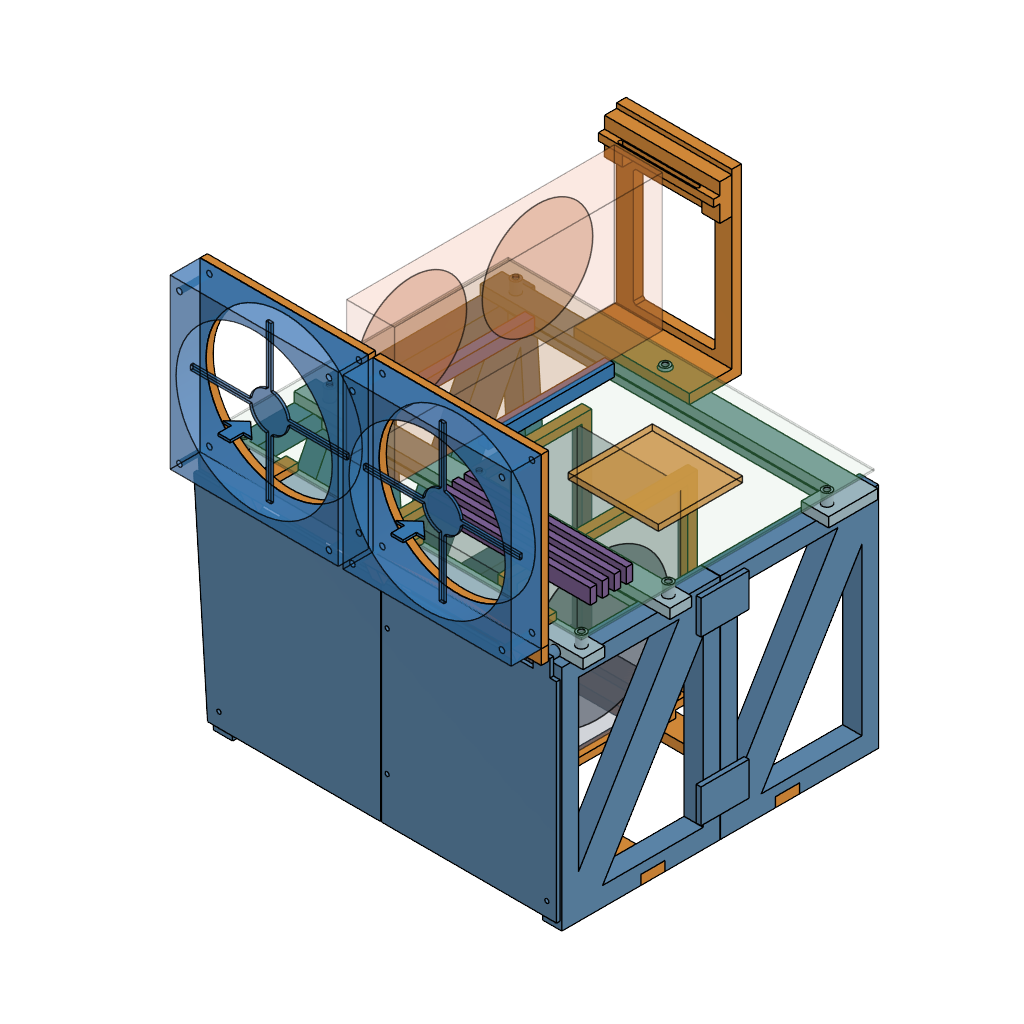
ATX_Desk_v04_layout (Autodesk Fusion 360 design; units mm, degrees)
part number: 2026-10-20-23-59-44-209
part number: 2026-10-20-23-59-44-522
part number: 2026-10-20-23-59-44-967
part number: 2026-10-20-23-59-45-768
part number: 2026-10-20-23-59-46-990
part number: 2026-10-20-23-59-48-547
part number: 2026-10-20-23-59-49-268
part number: 2026-10-20-23-59-50-114
part number: 2026-10-20-23-59-51-053
part number: 2026-10-20-23-59-51-964
part number: 2026-10-20-23-59-56-069
part number: 2026-10-21-00-00-01-103
part number: 2026-10-21-00-00-08-092
part number: 2026-10-21-00-00-09-158
part number: 2026-10-21-00-00-10-242
part number: 2026-10-21-00-00-23-562
part number: 2026-10-21-00-00-25-419
part number: 2026-10-21-00-00-27-273
part number: 2026-10-21-00-00-38-661
part number: 2026-10-21-00-00-46-426
part number: 2026-10-21-00-00-56-981
part number: 2026-10-21-00-01-04-262
part number: 2026-10-21-00-01-12-035
part number: 2026-10-21-00-01-25-487
part number: 2026-10-21-00-01-28-371
part number: 2026-10-21-00-01-43-062
part number: 2026-10-21-00-01-46-190
part number: 2026-10-21-00-02-02-158
part number: 2026-10-21-00-02-04-809
part number: 2026-10-21-00-02-14-600
part number: 2026-10-21-00-02-17-363
part number: 2026-10-21-00-02-20-116
part number: 2026-10-21-00-02-22-902
part number: 2026-10-21-00-02-25-724
part number: 2026-10-21-00-02-27-737
part number: 2026-10-21-00-14-16-300
part number: 2026-10-21-00-14-19-114
Autodesk Fusion 360 part; units mm, degrees
(part 1 of 2)
ref_plane "工作平面1" through (0, 0, 0) normal (0, 0, 1) x (1, 0, 0) in component "01_PCI_front_INSET_SIDE"
sketch "草图1" plane through (0, 0, 0) normal (0, 0, 1) x (1, 0, 0) in component "01_PCI_front_INSET_SIDE"
  line L0 (8.45, -10) -> (24.45, -10)
  line L1 (24.45, -10) -> (24.45, 121.72)
  line L2 (24.45, 121.72) -> (8.45, 121.72)
  line L3 (8.45, 121.72) -> (8.45, -10)
ref_plane "工作平面2" through (0, 0, 190) normal (0, 0, 1) x (1, 0, 0) in component "01_PCI_front_INSET_SIDE"
sketch "草图2" plane through (0, 0, 190) normal (0, 0, 1) x (1, 0, 0) in component "01_PCI_front_INSET_SIDE"
  line L0 (-4, -10) -> (12, -10)
  line L1 (12, -10) -> (12, 121.72)
  line L2 (12, 121.72) -> (-4, 121.72)
  line L3 (-4, 121.72) -> (-4, -10)
loft "Inward taper side frame" add profiles "草图1", "草图2" section 1 section 2 makes body 1 in component "01_PCI_front_INSET_SIDE"
ref_plane "工作平面3" through (-10, 0, 0) normal (1, 0, 0) x (0, 1, 0) in component "01_PCI_front_INSET_SIDE"
sketch "草图3" plane through (-10, 0, 0) normal (1, 0, 0) x (0, 0, -1) in component "01_PCI_front_INSET_SIDE"
  line L0 (-36, 4) -> (-176, 4)
  line L1 (-176, 4) -> (-176, 87.72)
  line L2 (-176, 87.72) -> (-36, 4)
extrude "Upper triangular opening" cut sketch "草图3" along normal blind 340 bodies 1 in component "01_PCI_front_INSET_SIDE"
ref_plane "工作平面4" through (-10, 0, 0) normal (1, 0, 0) x (0, 1, 0) in component "01_PCI_front_INSET_SIDE"
sketch "草图4" plane through (-10, 0, 0) normal (1, 0, 0) x (0, 0, -1) in component "01_PCI_front_INSET_SIDE"
  line L0 (-16, 24) -> (-16, 107.72)
  line L1 (-16, 107.72) -> (-154, 107.72)
  line L2 (-154, 107.72) -> (-16, 24)
extrude "Lower triangular opening" cut sketch "草图4" along normal blind 340 bodies 1 in component "01_PCI_front_INSET_SIDE"
ref_plane "工作平面5" through (0, 0, 0) normal (0, 0, 1) x (1, 0, 0) in component "01_PCI_front_INSET_SIDE"
sketch "草图5" plane through (0, 0, 0) normal (0, 0, 1) x (1, 0, 0) in component "01_PCI_front_INSET_SIDE"
  line L0 (-10, 55.92) -> (320, 55.92)
  line L1 (320, 55.92) -> (320, 75.92)
  line L2 (320, 75.92) -> (-10, 75.92)
  line L3 (-10, 75.92) -> (-10, 55.92)
extrude "Recess for bottom crossbar" cut sketch "草图5" along normal blind 8 bodies 1 in component "01_PCI_front_INSET_SIDE"
ref_plane "工作平面1" through (0, 0, 0) normal (0, 0, 1) x (1, 0, 0) in component "01_PCI_rear_INSET_SIDE"
sketch "草图1 (2)" plane through (0, 0, 0) normal (0, 0, 1) x (1, 0, 0) in component "01_PCI_rear_INSET_SIDE"
  line L0 (8.45, 122.12) -> (24.45, 122.12)
  line L1 (24.45, 122.12) -> (24.45, 253.84)
  line L2 (24.45, 253.84) -> (8.45, 253.84)
  line L3 (8.45, 253.84) -> (8.45, 122.12)
ref_plane "工作平面2" through (0, 0, 190) normal (0, 0, 1) x (1, 0, 0) in component "01_PCI_rear_INSET_SIDE"
sketch "草图2 (2)" plane through (0, 0, 190) normal (0, 0, 1) x (1, 0, 0) in component "01_PCI_rear_INSET_SIDE"
  line L0 (-4, 122.12) -> (12, 122.12)
  line L1 (12, 122.12) -> (12, 253.84)
  line L2 (12, 253.84) -> (-4, 253.84)
  line L3 (-4, 253.84) -> (-4, 122.12)
loft "Inward taper side frame'" add profiles "草图1 (2)", "草图2 (2)" section 1 section 2 separate body makes body 2 in component "01_PCI_rear_INSET_SIDE"
ref_plane "工作平面3" through (-10, 0, 0) normal (1, 0, 0) x (0, 1, 0) in component "01_PCI_rear_INSET_SIDE"
sketch "草图3 (2)" plane through (-10, 0, 0) normal (1, 0, 0) x (0, 0, -1) in component "01_PCI_rear_INSET_SIDE"
  line L0 (-36, 136.12) -> (-176, 136.12)
  line L1 (-176, 136.12) -> (-176, 219.84)
  line L2 (-176, 219.84) -> (-36, 136.12)
extrude "Upper triangular opening'" cut sketch "草图3 (2)" along normal blind 340 bodies 2 in component "01_PCI_rear_INSET_SIDE"
ref_plane "工作平面4" through (-10, 0, 0) normal (1, 0, 0) x (0, 1, 0) in component "01_PCI_rear_INSET_SIDE"
sketch "草图4 (2)" plane through (-10, 0, 0) normal (1, 0, 0) x (0, 0, -1) in component "01_PCI_rear_INSET_SIDE"
  line L0 (-16, 156.12) -> (-16, 239.84)
  line L1 (-16, 239.84) -> (-154, 239.84)
  line L2 (-154, 239.84) -> (-16, 156.12)
extrude "Lower triangular opening'" cut sketch "草图4 (2)" along normal blind 340 bodies 2 in component "01_PCI_rear_INSET_SIDE"
ref_plane "工作平面5" through (0, 0, 0) normal (0, 0, 1) x (1, 0, 0) in component "01_PCI_rear_INSET_SIDE"
sketch "草图5 (2)" plane through (0, 0, 0) normal (0, 0, 1) x (1, 0, 0) in component "01_PCI_rear_INSET_SIDE"
  line L0 (-10, 167.92) -> (320, 167.92)
  line L1 (320, 167.92) -> (320, 187.92)
  line L2 (320, 187.92) -> (-10, 187.92)
  line L3 (-10, 187.92) -> (-10, 167.92)
extrude "Recess for bottom crossbar'" cut sketch "草图5 (2)" along normal blind 8 bodies 2 in component "01_PCI_rear_INSET_SIDE"
ref_plane "工作平面1" through (0, 0, 0) normal (0, 0, 1) x (1, 0, 0) in component "01_CPU_front_VERTICAL_SIDE"
sketch "草图1 (3)" plane through (0, 0, 0) normal (0, 0, 1) x (1, 0, 0) in component "01_CPU_front_VERTICAL_SIDE"
  line L0 (282.45, -10) -> (298.45, -10)
  line L1 (298.45, -10) -> (298.45, 121.72)
  line L2 (298.45, 121.72) -> (282.45, 121.72)
  line L3 (282.45, 121.72) -> (282.45, -10)
ref_plane "工作平面2" through (0, 0, 190) normal (0, 0, 1) x (1, 0, 0) in component "01_CPU_front_VERTICAL_SIDE"
sketch "草图2 (3)" plane through (0, 0, 190) normal (0, 0, 1) x (1, 0, 0) in component "01_CPU_front_VERTICAL_SIDE"
  line L0 (282.45, -10) -> (298.45, -10)
  line L1 (298.45, -10) -> (298.45, 121.72)
  line L2 (298.45, 121.72) -> (282.45, 121.72)
  line L3 (282.45, 121.72) -> (282.45, -10)
loft "Inward taper side frame''" add profiles "草图1 (3)", "草图2 (3)" section 1 section 2 separate body makes body 3 in component "01_CPU_front_VERTICAL_SIDE"
ref_plane "工作平面3" through (-10, 0, 0) normal (1, 0, 0) x (0, 1, 0) in component "01_CPU_front_VERTICAL_SIDE"
sketch "草图3 (3)" plane through (-10, 0, 0) normal (1, 0, 0) x (0, 0, -1) in component "01_CPU_front_VERTICAL_SIDE"
  line L0 (-36, 4) -> (-176, 4)
  line L1 (-176, 4) -> (-176, 87.72)
  line L2 (-176, 87.72) -> (-36, 4)
extrude "Upper triangular opening''" cut sketch "草图3 (3)" along normal blind 340 bodies 3 in component "01_CPU_front_VERTICAL_SIDE"
ref_plane "工作平面4" through (-10, 0, 0) normal (1, 0, 0) x (0, 1, 0) in component "01_CPU_front_VERTICAL_SIDE"
sketch "草图4 (3)" plane through (-10, 0, 0) normal (1, 0, 0) x (0, 0, -1) in component "01_CPU_front_VERTICAL_SIDE"
  line L0 (-16, 24) -> (-16, 107.72)
  line L1 (-16, 107.72) -> (-154, 107.72)
  line L2 (-154, 107.72) -> (-16, 24)
extrude "Lower triangular opening''" cut sketch "草图4 (3)" along normal blind 340 bodies 3 in component "01_CPU_front_VERTICAL_SIDE"
ref_plane "工作平面5" through (0, 0, 0) normal (0, 0, 1) x (1, 0, 0) in component "01_CPU_front_VERTICAL_SIDE"
sketch "草图5 (3)" plane through (0, 0, 0) normal (0, 0, 1) x (1, 0, 0) in component "01_CPU_front_VERTICAL_SIDE"
  line L0 (-10, 55.92) -> (320, 55.92)
  line L1 (320, 55.92) -> (320, 75.92)
  line L2 (320, 75.92) -> (-10, 75.92)
  line L3 (-10, 75.92) -> (-10, 55.92)
extrude "Recess for bottom crossbar''" cut sketch "草图5 (3)" along normal blind 8 bodies 3 in component "01_CPU_front_VERTICAL_SIDE"
ref_plane "工作平面1" through (0, 0, 0) normal (0, 0, 1) x (1, 0, 0) in component "01_CPU_rear_VERTICAL_SIDE"
sketch "草图1 (4)" plane through (0, 0, 0) normal (0, 0, 1) x (1, 0, 0) in component "01_CPU_rear_VERTICAL_SIDE"
  line L0 (282.45, 122.12) -> (298.45, 122.12)
  line L1 (298.45, 122.12) -> (298.45, 253.84)
  line L2 (298.45, 253.84) -> (282.45, 253.84)
  line L3 (282.45, 253.84) -> (282.45, 122.12)
ref_plane "工作平面2" through (0, 0, 190) normal (0, 0, 1) x (1, 0, 0) in component "01_CPU_rear_VERTICAL_SIDE"
sketch "草图2 (4)" plane through (0, 0, 190) normal (0, 0, 1) x (1, 0, 0) in component "01_CPU_rear_VERTICAL_SIDE"
  line L0 (282.45, 122.12) -> (298.45, 122.12)
  line L1 (298.45, 122.12) -> (298.45, 253.84)
  line L2 (298.45, 253.84) -> (282.45, 253.84)
  line L3 (282.45, 253.84) -> (282.45, 122.12)
loft "Inward taper side frame'''" add profiles "草图1 (4)", "草图2 (4)" section 1 section 2 separate body makes body 4 in component "01_CPU_rear_VERTICAL_SIDE"
ref_plane "工作平面3" through (-10, 0, 0) normal (1, 0, 0) x (0, 1, 0) in component "01_CPU_rear_VERTICAL_SIDE"
sketch "草图3 (4)" plane through (-10, 0, 0) normal (1, 0, 0) x (0, 0, -1) in component "01_CPU_rear_VERTICAL_SIDE"
  line L0 (-36, 136.12) -> (-176, 136.12)
  line L1 (-176, 136.12) -> (-176, 219.84)
  line L2 (-176, 219.84) -> (-36, 136.12)
extrude "Upper triangular opening'''" cut sketch "草图3 (4)" along normal blind 340 bodies 4 in component "01_CPU_rear_VERTICAL_SIDE"
ref_plane "工作平面4" through (-10, 0, 0) normal (1, 0, 0) x (0, 1, 0) in component "01_CPU_rear_VERTICAL_SIDE"
sketch "草图4 (4)" plane through (-10, 0, 0) normal (1, 0, 0) x (0, 0, -1) in component "01_CPU_rear_VERTICAL_SIDE"
  line L0 (-16, 156.12) -> (-16, 239.84)
  line L1 (-16, 239.84) -> (-154, 239.84)
  line L2 (-154, 239.84) -> (-16, 156.12)
extrude "Lower triangular opening'''" cut sketch "草图4 (4)" along normal blind 340 bodies 4 in component "01_CPU_rear_VERTICAL_SIDE"
ref_plane "工作平面5" through (0, 0, 0) normal (0, 0, 1) x (1, 0, 0) in component "01_CPU_rear_VERTICAL_SIDE"
sketch "草图5 (4)" plane through (0, 0, 0) normal (0, 0, 1) x (1, 0, 0) in component "01_CPU_rear_VERTICAL_SIDE"
  line L0 (-10, 167.92) -> (320, 167.92)
  line L1 (320, 167.92) -> (320, 187.92)
  line L2 (320, 187.92) -> (-10, 187.92)
  line L3 (-10, 187.92) -> (-10, 167.92)
extrude "Recess for bottom crossbar'''" cut sketch "草图5 (4)" along normal blind 8 bodies 4 in component "01_CPU_rear_VERTICAL_SIDE"
ref_plane "工作平面1" through (0, 0, 22) normal (0, 0, 1) x (1, 0, 0) in component "02_PCI_low_SEAM_PLATE"
sketch "草图1 (5)" plane through (0, 0, 22) normal (0, 0, 1) x (1, 0, 0) in component "02_PCI_low_SEAM_PLATE"
  line L0 (3.0084, 101.92) -> (7.0084, 101.92)
  line L1 (7.0084, 101.92) -> (7.0084, 141.92)
  line L2 (7.0084, 141.92) -> (3.0084, 141.92)
  line L3 (3.0084, 141.92) -> (3.0084, 101.92)
ref_plane "工作平面2" through (0, 0, 50) normal (0, 0, 1) x (1, 0, 0) in component "02_PCI_low_SEAM_PLATE"
sketch "草图2 (5)" plane through (0, 0, 50) normal (0, 0, 1) x (1, 0, 0) in component "02_PCI_low_SEAM_PLATE"
  line L0 (1.1737, 101.92) -> (5.1737, 101.92)
  line L1 (5.1737, 101.92) -> (5.1737, 141.92)
  line L2 (5.1737, 141.92) -> (1.1737, 141.92)
  line L3 (1.1737, 141.92) -> (1.1737, 101.92)
loft "Taper matching seam plate - screw detail pending" add profiles "草图1 (5)", "草图2 (5)" section 1 section 2 separate body makes body 5 in component "02_PCI_low_SEAM_PLATE"
ref_plane "工作平面1" through (0, 0, 158) normal (0, 0, 1) x (1, 0, 0) in component "02_PCI_high_SEAM_PLATE"
sketch "草图1 (6)" plane through (0, 0, 158) normal (0, 0, 1) x (1, 0, 0) in component "02_PCI_high_SEAM_PLATE"
  line L0 (-5.9032, 101.92) -> (-1.9032, 101.92)
  line L1 (-1.9032, 101.92) -> (-1.9032, 141.92)
  line L2 (-1.9032, 141.92) -> (-5.9032, 141.92)
  line L3 (-5.9032, 141.92) -> (-5.9032, 101.92)
ref_plane "工作平面2" through (0, 0, 186) normal (0, 0, 1) x (1, 0, 0) in component "02_PCI_high_SEAM_PLATE"
sketch "草图2 (6)" plane through (0, 0, 186) normal (0, 0, 1) x (1, 0, 0) in component "02_PCI_high_SEAM_PLATE"
  line L0 (-7.7379, 101.92) -> (-3.7379, 101.92)
  line L1 (-3.7379, 101.92) -> (-3.7379, 141.92)
  line L2 (-3.7379, 141.92) -> (-7.7379, 141.92)
  line L3 (-7.7379, 141.92) -> (-7.7379, 101.92)
loft "Taper matching seam plate - screw detail pending'" add profiles "草图1 (6)", "草图2 (6)" section 1 section 2 separate body makes body 6 in component "02_PCI_high_SEAM_PLATE"
ref_plane "工作平面1" through (0, 0, 22) normal (0, 0, 1) x (1, 0, 0) in component "02_CPU_low_SEAM_PLATE"
sketch "草图1 (7)" plane through (0, 0, 22) normal (0, 0, 1) x (1, 0, 0) in component "02_CPU_low_SEAM_PLATE"
  line L0 (298.45, 101.92) -> (302.45, 101.92)
  line L1 (302.45, 101.92) -> (302.45, 141.92)
  line L2 (302.45, 141.92) -> (298.45, 141.92)
  line L3 (298.45, 141.92) -> (298.45, 101.92)
ref_plane "工作平面2" through (0, 0, 50) normal (0, 0, 1) x (1, 0, 0) in component "02_CPU_low_SEAM_PLATE"
sketch "草图2 (7)" plane through (0, 0, 50) normal (0, 0, 1) x (1, 0, 0) in component "02_CPU_low_SEAM_PLATE"
  line L0 (298.45, 101.92) -> (302.45, 101.92)
  line L1 (302.45, 101.92) -> (302.45, 141.92)
  line L2 (302.45, 141.92) -> (298.45, 141.92)
  line L3 (298.45, 141.92) -> (298.45, 101.92)
loft "Taper matching seam plate - screw detail pending''" add profiles "草图1 (7)", "草图2 (7)" section 1 section 2 separate body makes body 7 in component "02_CPU_low_SEAM_PLATE"
ref_plane "工作平面1" through (0, 0, 158) normal (0, 0, 1) x (1, 0, 0) in component "02_CPU_high_SEAM_PLATE"
sketch "草图1 (8)" plane through (0, 0, 158) normal (0, 0, 1) x (1, 0, 0) in component "02_CPU_high_SEAM_PLATE"
  line L0 (298.45, 101.92) -> (302.45, 101.92)
  line L1 (302.45, 101.92) -> (302.45, 141.92)
  line L2 (302.45, 141.92) -> (298.45, 141.92)
  line L3 (298.45, 141.92) -> (298.45, 101.92)
ref_plane "工作平面2" through (0, 0, 186) normal (0, 0, 1) x (1, 0, 0) in component "02_CPU_high_SEAM_PLATE"
sketch "草图2 (8)" plane through (0, 0, 186) normal (0, 0, 1) x (1, 0, 0) in component "02_CPU_high_SEAM_PLATE"
  line L0 (298.45, 101.92) -> (302.45, 101.92)
  line L1 (302.45, 101.92) -> (302.45, 141.92)
  line L2 (302.45, 141.92) -> (298.45, 141.92)
  line L3 (298.45, 141.92) -> (298.45, 101.92)
loft "Taper matching seam plate - screw detail pending'''" add profiles "草图1 (8)", "草图2 (8)" section 1 section 2 separate body makes body 8 in component "02_CPU_high_SEAM_PLATE"
ref_plane "工作平面1" through (0, 0, 190) normal (0, 0, 1) x (1, 0, 0) in component "03_FRONT_MOTHERBOARD_BEAM"
sketch "草图1 (9)" plane through (0, 0, 190) normal (0, 0, 1) x (1, 0, 0) in component "03_FRONT_MOTHERBOARD_BEAM"
  line L0 (-4, -2.65) -> (308.8, -2.65)
  line L1 (308.8, -2.65) -> (308.8, 15.35)
  line L2 (308.8, 15.35) -> (-4, 15.35)
  line L3 (-4, 15.35) -> (-4, -2.65)
extrude "Upper beam flange" add sketch "草图1 (9)" along normal blind 8 separate body makes body 9 in component "03_FRONT_MOTHERBOARD_BEAM"
ref_plane "工作平面2" through (0, 0, 178) normal (0, 0, 1) x (1, 0, 0) in component "03_FRONT_MOTHERBOARD_BEAM"
sketch "草图2 (9)" plane through (0, 0, 178) normal (0, 0, 1) x (1, 0, 0) in component "03_FRONT_MOTHERBOARD_BEAM"
  line L0 (14, 2.35) -> (281.45, 2.35)
  line L1 (281.45, 2.35) -> (281.45, 10.35)
  line L2 (281.45, 10.35) -> (14, 10.35)
  line L3 (14, 10.35) -> (14, 2.35)
extrude "Underside rib" add sketch "草图2 (9)" along normal blind 12 bodies 9 in component "03_FRONT_MOTHERBOARD_BEAM"
ref_plane "工作平面3" through (14, 0, 0) normal (1, 0, 0) x (0, 1, 0) in component "03_FRONT_MOTHERBOARD_BEAM"
sketch "草图3 (5)" plane through (14, 0, 0) normal (1, 0, 0) x (0, 0, -1) in component "03_FRONT_MOTHERBOARD_BEAM"
  line L0 (-184, 2.35) -> (-184, 10.35)
  line L1 (-184, 10.35) -> (-190, 15.35)
  line L2 (-190, 15.35) -> (-190, -2.65)
  line L3 (-190, -2.65) -> (-184, 2.35)
extrude "Printable rib transition" add sketch "草图3 (5)" along normal blind 267.45 bodies 9 in component "03_FRONT_MOTHERBOARD_BEAM"
ref_plane "工作平面4" through (0, 0, 198) normal (0, 0, 1) x (1, 0, 0) in component "03_FRONT_MOTHERBOARD_BEAM"
sketch "草图4 (5)" plane through (0, 0, 198) normal (0, 0, 1) x (1, 0, 0) in component "03_FRONT_MOTHERBOARD_BEAM"
  circle A0 centre (16.51, 6.35) radius 4
extrude "Motherboard mount 7" add sketch "草图4 (5)" along normal blind 10 bodies 9 in component "03_FRONT_MOTHERBOARD_BEAM"
ref_plane "工作平面5" through (0, 0, 203.1) normal (0, 0, 1) x (1, 0, 0) in component "03_FRONT_MOTHERBOARD_BEAM"
sketch "草图5 (5)" plane through (0, 0, 203.1) normal (0, 0, 1) x (1, 0, 0) in component "03_FRONT_MOTHERBOARD_BEAM"
  circle A0 centre (16.51, 6.35) radius 2.35
extrude "M3 insert pocket 7" cut sketch "草图5 (5)" along normal blind 4.9 bodies 9 in component "03_FRONT_MOTHERBOARD_BEAM"
ref_plane "工作平面6" through (0, 0, 198) normal (0, 0, 1) x (1, 0, 0) in component "03_FRONT_MOTHERBOARD_BEAM"
sketch "草图6" plane through (0, 0, 198) normal (0, 0, 1) x (1, 0, 0) in component "03_FRONT_MOTHERBOARD_BEAM"
  circle A0 centre (140.97, 6.35) radius 4
extrude "Motherboard mount 8" add sketch "草图6" along normal blind 10 bodies 9 in component "03_FRONT_MOTHERBOARD_BEAM"
ref_plane "工作平面7" through (0, 0, 203.1) normal (0, 0, 1) x (1, 0, 0) in component "03_FRONT_MOTHERBOARD_BEAM"
sketch "草图7" plane through (0, 0, 203.1) normal (0, 0, 1) x (1, 0, 0) in component "03_FRONT_MOTHERBOARD_BEAM"
  circle A0 centre (140.97, 6.35) radius 2.35
extrude "M3 insert pocket 8" cut sketch "草图7" along normal blind 4.9 bodies 9 in component "03_FRONT_MOTHERBOARD_BEAM"
ref_plane "工作平面8" through (0, 0, 198) normal (0, 0, 1) x (1, 0, 0) in component "03_FRONT_MOTHERBOARD_BEAM"
sketch "草图8" plane through (0, 0, 198) normal (0, 0, 1) x (1, 0, 0) in component "03_FRONT_MOTHERBOARD_BEAM"
  circle A0 centre (298.45, 6.35) radius 4
extrude "Motherboard mount 9" add sketch "草图8" along normal blind 10 bodies 9 in component "03_FRONT_MOTHERBOARD_BEAM"
ref_plane "工作平面9" through (0, 0, 203.1) normal (0, 0, 1) x (1, 0, 0) in component "03_FRONT_MOTHERBOARD_BEAM"
sketch "草图9" plane through (0, 0, 203.1) normal (0, 0, 1) x (1, 0, 0) in component "03_FRONT_MOTHERBOARD_BEAM"
  circle A0 centre (298.45, 6.35) radius 2.35
extrude "M3 insert pocket 9" cut sketch "草图9" along normal blind 4.9 bodies 9 in component "03_FRONT_MOTHERBOARD_BEAM"
ref_plane "工作平面1" through (0, 0, 190) normal (0, 0, 1) x (1, 0, 0) in component "03_MID_MOTHERBOARD_BEAM"
sketch "草图1 (10)" plane through (0, 0, 190) normal (0, 0, 1) x (1, 0, 0) in component "03_MID_MOTHERBOARD_BEAM"
  line L0 (-4, 69.74) -> (308.8, 69.74)
  line L1 (308.8, 69.74) -> (308.8, 87.74)
  line L2 (308.8, 87.74) -> (-4, 87.74)
  line L3 (-4, 87.74) -> (-4, 69.74)
extrude "Upper beam flange'" add sketch "草图1 (10)" along normal blind 8 separate body makes body 10 in component "03_MID_MOTHERBOARD_BEAM"
ref_plane "工作平面2" through (0, 0, 178) normal (0, 0, 1) x (1, 0, 0) in component "03_MID_MOTHERBOARD_BEAM"
sketch "草图2 (10)" plane through (0, 0, 178) normal (0, 0, 1) x (1, 0, 0) in component "03_MID_MOTHERBOARD_BEAM"
  line L0 (14, 74.74) -> (281.45, 74.74)
  line L1 (281.45, 74.74) -> (281.45, 82.74)
  line L2 (281.45, 82.74) -> (14, 82.74)
  line L3 (14, 82.74) -> (14, 74.74)
extrude "Underside rib'" add sketch "草图2 (10)" along normal blind 12 bodies 10 in component "03_MID_MOTHERBOARD_BEAM"
ref_plane "工作平面3" through (14, 0, 0) normal (1, 0, 0) x (0, 1, 0) in component "03_MID_MOTHERBOARD_BEAM"
sketch "草图3 (6)" plane through (14, 0, 0) normal (1, 0, 0) x (0, 0, -1) in component "03_MID_MOTHERBOARD_BEAM"
  line L0 (-184, 74.74) -> (-184, 82.74)
  line L1 (-184, 82.74) -> (-190, 87.74)
  line L2 (-190, 87.74) -> (-190, 69.74)
  line L3 (-190, 69.74) -> (-184, 74.74)
extrude "Printable rib transition'" add sketch "草图3 (6)" along normal blind 267.45 bodies 10 in component "03_MID_MOTHERBOARD_BEAM"
ref_plane "工作平面4" through (0, 0, 198) normal (0, 0, 1) x (1, 0, 0) in component "03_MID_MOTHERBOARD_BEAM"
sketch "草图4 (6)" plane through (0, 0, 198) normal (0, 0, 1) x (1, 0, 0) in component "03_MID_MOTHERBOARD_BEAM"
  circle A0 centre (16.51, 78.74) radius 4
extrude "Motherboard mount 4" add sketch "草图4 (6)" along normal blind 10 bodies 10 in component "03_MID_MOTHERBOARD_BEAM"
ref_plane "工作平面5" through (0, 0, 203.1) normal (0, 0, 1) x (1, 0, 0) in component "03_MID_MOTHERBOARD_BEAM"
sketch "草图5 (6)" plane through (0, 0, 203.1) normal (0, 0, 1) x (1, 0, 0) in component "03_MID_MOTHERBOARD_BEAM"
  circle A0 centre (16.51, 78.74) radius 2.35
extrude "M3 insert pocket 4" cut sketch "草图5 (6)" along normal blind 4.9 bodies 10 in component "03_MID_MOTHERBOARD_BEAM"
ref_plane "工作平面6" through (0, 0, 198) normal (0, 0, 1) x (1, 0, 0) in component "03_MID_MOTHERBOARD_BEAM"
sketch "草图6 (2)" plane through (0, 0, 198) normal (0, 0, 1) x (1, 0, 0) in component "03_MID_MOTHERBOARD_BEAM"
  circle A0 centre (140.97, 78.74) radius 4
extrude "Motherboard mount 5" add sketch "草图6 (2)" along normal blind 10 bodies 10 in component "03_MID_MOTHERBOARD_BEAM"
ref_plane "工作平面7" through (0, 0, 203.1) normal (0, 0, 1) x (1, 0, 0) in component "03_MID_MOTHERBOARD_BEAM"
sketch "草图7 (2)" plane through (0, 0, 203.1) normal (0, 0, 1) x (1, 0, 0) in component "03_MID_MOTHERBOARD_BEAM"
  circle A0 centre (140.97, 78.74) radius 2.35
extrude "M3 insert pocket 5" cut sketch "草图7 (2)" along normal blind 4.9 bodies 10 in component "03_MID_MOTHERBOARD_BEAM"
ref_plane "工作平面8" through (0, 0, 198) normal (0, 0, 1) x (1, 0, 0) in component "03_MID_MOTHERBOARD_BEAM"
sketch "草图8 (2)" plane through (0, 0, 198) normal (0, 0, 1) x (1, 0, 0) in component "03_MID_MOTHERBOARD_BEAM"
  circle A0 centre (298.45, 78.74) radius 4
extrude "Motherboard mount 6" add sketch "草图8 (2)" along normal blind 10 bodies 10 in component "03_MID_MOTHERBOARD_BEAM"
ref_plane "工作平面9" through (0, 0, 203.1) normal (0, 0, 1) x (1, 0, 0) in component "03_MID_MOTHERBOARD_BEAM"
sketch "草图9 (2)" plane through (0, 0, 203.1) normal (0, 0, 1) x (1, 0, 0) in component "03_MID_MOTHERBOARD_BEAM"
  circle A0 centre (298.45, 78.74) radius 2.35
extrude "M3 insert pocket 6" cut sketch "草图9 (2)" along normal blind 4.9 bodies 10 in component "03_MID_MOTHERBOARD_BEAM"
ref_plane "工作平面1" through (0, 0, 190) normal (0, 0, 1) x (1, 0, 0) in component "03_REAR_MOTHERBOARD_BEAM"
sketch "草图1 (11)" plane through (0, 0, 190) normal (0, 0, 1) x (1, 0, 0) in component "03_REAR_MOTHERBOARD_BEAM"
  line L0 (-4, 224.68) -> (308.8, 224.68)
  line L1 (308.8, 224.68) -> (308.8, 242.68)
  line L2 (308.8, 242.68) -> (-4, 242.68)
  line L3 (-4, 242.68) -> (-4, 224.68)
extrude "Upper beam flange''" add sketch "草图1 (11)" along normal blind 8 separate body makes body 11 in component "03_REAR_MOTHERBOARD_BEAM"
ref_plane "工作平面2" through (0, 0, 178) normal (0, 0, 1) x (1, 0, 0) in component "03_REAR_MOTHERBOARD_BEAM"
sketch "草图2 (11)" plane through (0, 0, 178) normal (0, 0, 1) x (1, 0, 0) in component "03_REAR_MOTHERBOARD_BEAM"
  line L0 (14, 229.68) -> (281.45, 229.68)
  line L1 (281.45, 229.68) -> (281.45, 237.68)
  line L2 (281.45, 237.68) -> (14, 237.68)
  line L3 (14, 237.68) -> (14, 229.68)
extrude "Underside rib''" add sketch "草图2 (11)" along normal blind 12 bodies 11 in component "03_REAR_MOTHERBOARD_BEAM"
ref_plane "工作平面3" through (14, 0, 0) normal (1, 0, 0) x (0, 1, 0) in component "03_REAR_MOTHERBOARD_BEAM"
sketch "草图3 (7)" plane through (14, 0, 0) normal (1, 0, 0) x (0, 0, -1) in component "03_REAR_MOTHERBOARD_BEAM"
  line L0 (-184, 229.68) -> (-184, 237.68)
  line L1 (-184, 237.68) -> (-190, 242.68)
  line L2 (-190, 242.68) -> (-190, 224.68)
  line L3 (-190, 224.68) -> (-184, 229.68)
extrude "Printable rib transition''" add sketch "草图3 (7)" along normal blind 267.45 bodies 11 in component "03_REAR_MOTHERBOARD_BEAM"
ref_plane "工作平面4" through (0, 0, 190) normal (0, 0, 1) x (1, 0, 0) in component "03_REAR_MOTHERBOARD_BEAM"
sketch "草图4 (7)" plane through (0, 0, 190) normal (0, 0, 1) x (1, 0, 0) in component "03_REAR_MOTHERBOARD_BEAM"
  line L0 (286, 201.82) -> (308.8, 201.82)
  line L1 (308.8, 201.82) -> (308.8, 233.68)
  line L2 (308.8, 233.68) -> (286, 233.68)
  line L3 (286, 233.68) -> (286, 201.82)
extrude "Staggered hole 3 pad" add sketch "草图4 (7)" along normal blind 8 bodies 11 in component "03_REAR_MOTHERBOARD_BEAM"
ref_plane "工作平面5" through (0, 0, 198) normal (0, 0, 1) x (1, 0, 0) in component "03_REAR_MOTHERBOARD_BEAM"
sketch "草图5 (7)" plane through (0, 0, 198) normal (0, 0, 1) x (1, 0, 0) in component "03_REAR_MOTHERBOARD_BEAM"
  circle A0 centre (16.51, 233.68) radius 4
extrude "Motherboard mount 1" add sketch "草图5 (7)" along normal blind 10 bodies 11 in component "03_REAR_MOTHERBOARD_BEAM"
ref_plane "工作平面6" through (0, 0, 203.1) normal (0, 0, 1) x (1, 0, 0) in component "03_REAR_MOTHERBOARD_BEAM"
sketch "草图6 (3)" plane through (0, 0, 203.1) normal (0, 0, 1) x (1, 0, 0) in component "03_REAR_MOTHERBOARD_BEAM"
  circle A0 centre (16.51, 233.68) radius 2.35
extrude "M3 insert pocket 1" cut sketch "草图6 (3)" along normal blind 4.9 bodies 11 in component "03_REAR_MOTHERBOARD_BEAM"
ref_plane "工作平面7" through (0, 0, 198) normal (0, 0, 1) x (1, 0, 0) in component "03_REAR_MOTHERBOARD_BEAM"
sketch "草图7 (3)" plane through (0, 0, 198) normal (0, 0, 1) x (1, 0, 0) in component "03_REAR_MOTHERBOARD_BEAM"
  circle A0 centre (140.97, 233.68) radius 4
extrude "Motherboard mount 2" add sketch "草图7 (3)" along normal blind 10 bodies 11 in component "03_REAR_MOTHERBOARD_BEAM"
ref_plane "工作平面8" through (0, 0, 203.1) normal (0, 0, 1) x (1, 0, 0) in component "03_REAR_MOTHERBOARD_BEAM"
sketch "草图8 (3)" plane through (0, 0, 203.1) normal (0, 0, 1) x (1, 0, 0) in component "03_REAR_MOTHERBOARD_BEAM"
  circle A0 centre (140.97, 233.68) radius 2.35
extrude "M3 insert pocket 2" cut sketch "草图8 (3)" along normal blind 4.9 bodies 11 in component "03_REAR_MOTHERBOARD_BEAM"
ref_plane "工作平面9" through (0, 0, 198) normal (0, 0, 1) x (1, 0, 0) in component "03_REAR_MOTHERBOARD_BEAM"
sketch "草图9 (3)" plane through (0, 0, 198) normal (0, 0, 1) x (1, 0, 0) in component "03_REAR_MOTHERBOARD_BEAM"
  circle A0 centre (298.45, 210.82) radius 4
extrude "Motherboard mount 3" add sketch "草图9 (3)" along normal blind 10 bodies 11 in component "03_REAR_MOTHERBOARD_BEAM"
ref_plane "工作平面10" through (0, 0, 203.1) normal (0, 0, 1) x (1, 0, 0) in component "03_REAR_MOTHERBOARD_BEAM"
sketch "草图10" plane through (0, 0, 203.1) normal (0, 0, 1) x (1, 0, 0) in component "03_REAR_MOTHERBOARD_BEAM"
  circle A0 centre (298.45, 210.82) radius 2.35
extrude "M3 insert pocket 3" cut sketch "草图10" along normal blind 4.9 bodies 11 in component "03_REAR_MOTHERBOARD_BEAM"
ref_plane "工作平面1" through (0, 0, 0) normal (0, 0, 1) x (1, 0, 0) in component "04_front_GROUND_BAR_290mm"
sketch "草图1 (12)" plane through (0, 0, 0) normal (0, 0, 1) x (1, 0, 0) in component "04_front_GROUND_BAR_290mm"
  line L0 (8.45, 55.92) -> (298.45, 55.92)
  line L1 (298.45, 55.92) -> (298.45, 75.92)
  line L2 (298.45, 75.92) -> (8.45, 75.92)
  line L3 (8.45, 75.92) -> (8.45, 55.92)
extrude "290 mm floor crossbar" add sketch "草图1 (12)" along normal blind 8 separate body makes body 12 in component "04_front_GROUND_BAR_290mm"
ref_plane "工作平面1" through (0, 0, 0) normal (0, 0, 1) x (1, 0, 0) in component "04_rear_GROUND_BAR_290mm"
sketch "草图1 (13)" plane through (0, 0, 0) normal (0, 0, 1) x (1, 0, 0) in component "04_rear_GROUND_BAR_290mm"
  line L0 (8.45, 167.92) -> (298.45, 167.92)
  line L1 (298.45, 167.92) -> (298.45, 187.92)
  line L2 (298.45, 187.92) -> (8.45, 187.92)
  line L3 (8.45, 187.92) -> (8.45, 167.92)
extrude "290 mm floor crossbar'" add sketch "草图1 (13)" along normal blind 8 separate body makes body 13 in component "04_rear_GROUND_BAR_290mm"
ref_plane "工作平面1" through (0, 0, 14) normal (0, 0, 1) x (1, 0, 0) in component "05_CENTERED_PSU_CRADLE"
sketch "草图1 (14)" plane through (0, 0, 14) normal (0, 0, 1) x (1, 0, 0) in component "05_CENTERED_PSU_CRADLE"
  line L0 (104.4, 42.92) -> (112.4, 42.92)
  line L1 (112.4, 42.92) -> (112.4, 200.92)
  line L2 (112.4, 200.92) -> (104.4, 200.92)
  line L3 (104.4, 200.92) -> (104.4, 42.92)
extrude "Left cradle runner" add sketch "草图1 (14)" along normal blind 6 separate body makes body 14 in component "05_CENTERED_PSU_CRADLE"
ref_plane "工作平面2" through (0, 0, 14) normal (0, 0, 1) x (1, 0, 0) in component "05_CENTERED_PSU_CRADLE"
sketch "草图2 (12)" plane through (0, 0, 14) normal (0, 0, 1) x (1, 0, 0) in component "05_CENTERED_PSU_CRADLE"
  line L0 (112.4, 51.92) -> (200.4, 51.92)
  line L1 (200.4, 51.92) -> (200.4, 67.92)
  line L2 (200.4, 67.92) -> (112.4, 67.92)
  line L3 (112.4, 67.92) -> (112.4, 51.92)
extrude "Front PSU bearing rail" add sketch "草图2 (12)" along normal blind 6 bodies 14 in component "05_CENTERED_PSU_CRADLE"
ref_plane "工作平面3" through (0, 0, 14) normal (0, 0, 1) x (1, 0, 0) in component "05_CENTERED_PSU_CRADLE"
sketch "草图3 (8)" plane through (0, 0, 14) normal (0, 0, 1) x (1, 0, 0) in component "05_CENTERED_PSU_CRADLE"
  line L0 (192.4, 42.92) -> (200.4, 42.92)
  line L1 (200.4, 42.92) -> (200.4, 200.92)
  line L2 (200.4, 200.92) -> (192.4, 200.92)
  line L3 (192.4, 200.92) -> (192.4, 42.92)
extrude "Right cradle runner" add sketch "草图3 (8)" along normal blind 6 bodies 14 in component "05_CENTERED_PSU_CRADLE"
ref_plane "工作平面4" through (0, 0, 14) normal (0, 0, 1) x (1, 0, 0) in component "05_CENTERED_PSU_CRADLE"
sketch "草图4 (8)" plane through (0, 0, 14) normal (0, 0, 1) x (1, 0, 0) in component "05_CENTERED_PSU_CRADLE"
  line L0 (112.4, 175.92) -> (192.4, 175.92)
  line L1 (192.4, 175.92) -> (192.4, 191.92)
  line L2 (192.4, 191.92) -> (112.4, 191.92)
  line L3 (112.4, 191.92) -> (112.4, 175.92)
extrude "Rear PSU bearing rail" add sketch "草图4 (8)" along normal blind 6 bodies 14 in component "05_CENTERED_PSU_CRADLE"
ref_plane "工作平面5" through (0, 0, 8) normal (0, 0, 1) x (1, 0, 0) in component "05_CENTERED_PSU_CRADLE"
sketch "草图5 (8)" plane through (0, 0, 8) normal (0, 0, 1) x (1, 0, 0) in component "05_CENTERED_PSU_CRADLE"
  line L0 (104.4, 60.92) -> (112.4, 60.92)
  line L1 (112.4, 60.92) -> (112.4, 70.92)
  line L2 (112.4, 70.92) -> (104.4, 70.92)
  line L3 (104.4, 70.92) -> (104.4, 60.92)
extrude "Cradle load foot" add sketch "草图5 (8)" along normal blind 6 bodies 14 in component "05_CENTERED_PSU_CRADLE"
ref_plane "工作平面6" through (0, 0, 8) normal (0, 0, 1) x (1, 0, 0) in component "05_CENTERED_PSU_CRADLE"
sketch "草图6 (4)" plane through (0, 0, 8) normal (0, 0, 1) x (1, 0, 0) in component "05_CENTERED_PSU_CRADLE"
  line L0 (104.4, 172.92) -> (112.4, 172.92)
  line L1 (112.4, 172.92) -> (112.4, 182.92)
  line L2 (112.4, 182.92) -> (104.4, 182.92)
  line L3 (104.4, 182.92) -> (104.4, 172.92)
extrude "Cradle load foot (1)" add sketch "草图6 (4)" along normal blind 6 bodies 14 in component "05_CENTERED_PSU_CRADLE"
ref_plane "工作平面7" through (0, 0, 8) normal (0, 0, 1) x (1, 0, 0) in component "05_CENTERED_PSU_CRADLE"
sketch "草图7 (4)" plane through (0, 0, 8) normal (0, 0, 1) x (1, 0, 0) in component "05_CENTERED_PSU_CRADLE"
  line L0 (192.4, 60.92) -> (200.4, 60.92)
  line L1 (200.4, 60.92) -> (200.4, 70.92)
  line L2 (200.4, 70.92) -> (192.4, 70.92)
  line L3 (192.4, 70.92) -> (192.4, 60.92)
extrude "Cradle load foot (2)" add sketch "草图7 (4)" along normal blind 6 bodies 14 in component "05_CENTERED_PSU_CRADLE"
ref_plane "工作平面8" through (0, 0, 8) normal (0, 0, 1) x (1, 0, 0) in component "05_CENTERED_PSU_CRADLE"
sketch "草图8 (4)" plane through (0, 0, 8) normal (0, 0, 1) x (1, 0, 0) in component "05_CENTERED_PSU_CRADLE"
  line L0 (192.4, 172.92) -> (200.4, 172.92)
  line L1 (200.4, 172.92) -> (200.4, 182.92)
  line L2 (200.4, 182.92) -> (192.4, 182.92)
  line L3 (192.4, 182.92) -> (192.4, 172.92)
extrude "Cradle load foot (3)" add sketch "草图8 (4)" along normal blind 6 bodies 14 in component "05_CENTERED_PSU_CRADLE"
ref_plane "工作平面9" through (0, 0, 20) normal (0, 0, 1) x (1, 0, 0) in component "05_CENTERED_PSU_CRADLE"
sketch "草图9 (4)" plane through (0, 0, 20) normal (0, 0, 1) x (1, 0, 0) in component "05_CENTERED_PSU_CRADLE"
  line L0 (107.4, 53.92) -> (109.4, 53.92)
  line L1 (109.4, 53.92) -> (109.4, 57.92)
  line L2 (109.4, 57.92) -> (107.4, 57.92)
  line L3 (107.4, 57.92) -> (107.4, 53.92)
extrude "PSU bottom-edge stop" add sketch "草图9 (4)" along normal blind 6 bodies 14 in component "05_CENTERED_PSU_CRADLE"
ref_plane "工作平面10" through (0, 0, 20) normal (0, 0, 1) x (1, 0, 0) in component "05_CENTERED_PSU_CRADLE"
sketch "草图10 (2)" plane through (0, 0, 20) normal (0, 0, 1) x (1, 0, 0) in component "05_CENTERED_PSU_CRADLE"
  line L0 (107.4, 185.92) -> (109.4, 185.92)
  line L1 (109.4, 185.92) -> (109.4, 189.92)
  line L2 (109.4, 189.92) -> (107.4, 189.92)
  line L3 (107.4, 189.92) -> (107.4, 185.92)
extrude "PSU bottom-edge stop (1)" add sketch "草图10 (2)" along normal blind 6 bodies 14 in component "05_CENTERED_PSU_CRADLE"
ref_plane "工作平面11" through (0, 0, 20) normal (0, 0, 1) x (1, 0, 0) in component "05_CENTERED_PSU_CRADLE"
sketch "草图11" plane through (0, 0, 20) normal (0, 0, 1) x (1, 0, 0) in component "05_CENTERED_PSU_CRADLE"
  line L0 (195.4, 53.92) -> (197.4, 53.92)
  line L1 (197.4, 53.92) -> (197.4, 57.92)
  line L2 (197.4, 57.92) -> (195.4, 57.92)
  line L3 (195.4, 57.92) -> (195.4, 53.92)
extrude "PSU bottom-edge stop (2)" add sketch "草图11" along normal blind 6 bodies 14 in component "05_CENTERED_PSU_CRADLE"
ref_plane "工作平面12" through (0, 0, 20) normal (0, 0, 1) x (1, 0, 0) in component "05_CENTERED_PSU_CRADLE"
sketch "草图12" plane through (0, 0, 20) normal (0, 0, 1) x (1, 0, 0) in component "05_CENTERED_PSU_CRADLE"
  line L0 (195.4, 185.92) -> (197.4, 185.92)
  line L1 (197.4, 185.92) -> (197.4, 189.92)
  line L2 (197.4, 189.92) -> (195.4, 189.92)
  line L3 (195.4, 189.92) -> (195.4, 185.92)
extrude "PSU bottom-edge stop (3)" add sketch "草图12" along normal blind 6 bodies 14 in component "05_CENTERED_PSU_CRADLE"
ref_plane "工作平面1" through (104.4, 0, 0) normal (1, 0, 0) x (0, 1, 0) in component "06_PCI_PSU_RETAINER"
sketch "草图1 (15)" plane through (104.4, 0, 0) normal (1, 0, 0) x (0, 0, -1) in component "06_PCI_PSU_RETAINER"
  line L0 (-20, 42.92) -> (-20, 50.92)
  line L1 (-20, 50.92) -> (-171, 50.92)
  line L2 (-171, 50.92) -> (-171, 192.92)
  line L3 (-171, 192.92) -> (-20, 192.92)
  line L4 (-20, 192.92) -> (-20, 200.92)
  line L5 (-20, 200.92) -> (-178, 200.92)
  line L6 (-178, 200.92) -> (-178, 42.92)
  line L7 (-178, 42.92) -> (-20, 42.92)
extrude "Removable retainer outside intake face" add sketch "草图1 (15)" along normal blind 8 separate body makes body 15 in component "06_PCI_PSU_RETAINER"
ref_plane "工作平面1" through (192.4, 0, 0) normal (1, 0, 0) x (0, 1, 0) in component "06_CPU_PSU_RETAINER"
sketch "草图1 (16)" plane through (192.4, 0, 0) normal (1, 0, 0) x (0, 0, -1) in component "06_CPU_PSU_RETAINER"
  line L0 (-20, 42.92) -> (-20, 50.92)
  line L1 (-20, 50.92) -> (-171, 50.92)
  line L2 (-171, 50.92) -> (-171, 192.92)
  line L3 (-171, 192.92) -> (-20, 192.92)
  line L4 (-20, 192.92) -> (-20, 200.92)
  line L5 (-20, 200.92) -> (-178, 200.92)
  line L6 (-178, 200.92) -> (-178, 42.92)
  line L7 (-178, 42.92) -> (-20, 42.92)
extrude "Removable retainer outside intake face'" add sketch "草图1 (16)" along normal blind 8 separate body makes body 16 in component "06_CPU_PSU_RETAINER"
ref_plane "工作平面1" through (0, 0, 198) normal (0, 0, 1) x (1, 0, 0) in component "07_GPU_REAR_TOWER"
sketch "草图1 (17)" plane through (0, 0, 198) normal (0, 0, 1) x (1, 0, 0) in component "07_GPU_REAR_TOWER"
  line L0 (74, 224.68) -> (170, 224.68)
  line L1 (170, 224.68) -> (170, 268)
  line L2 (170, 268) -> (74, 268)
  line L3 (74, 268) -> (74, 224.68)
extrude "Rear tower foot - fasteners pending" add sketch "草图1 (17)" along normal blind 8 separate body makes body 17 in component "07_GPU_REAR_TOWER"
ref_plane "工作平面2" through (0, 0, 198) normal (0, 0, 1) x (1, 0, 0) in component "07_GPU_REAR_TOWER"
sketch "草图2 (13)" plane through (0, 0, 198) normal (0, 0, 1) x (1, 0, 0) in component "07_GPU_REAR_TOWER"
  circle A0 centre (140.97, 233.68) radius 4.75
extrude "Hole 2 standoff clearance" cut sketch "草图2 (13)" along normal blind 8 bodies 17 in component "07_GPU_REAR_TOWER"
ref_plane "工作平面3" through (0, 0, 206) normal (0, 0, 1) x (1, 0, 0) in component "07_GPU_REAR_TOWER"
sketch "草图3 (9)" plane through (0, 0, 206) normal (0, 0, 1) x (1, 0, 0) in component "07_GPU_REAR_TOWER"
  line L0 (74, 260) -> (170, 260)
  line L1 (170, 260) -> (170, 268)
  line L2 (170, 268) -> (74, 268)
  line L3 (74, 268) -> (74, 260)
extrude "Rear display connector frame" add sketch "草图3 (9)" along normal blind 144 bodies 17 in component "07_GPU_REAR_TOWER"
ref_plane "工作平面4" through (0, -260, 0) normal (0, 1, 0) x (0, 0, 1) in component "07_GPU_REAR_TOWER"
sketch "草图4 (9)" plane through (0, -260, 0) normal (0, 1, 0) x (1, 0, 0) in component "07_GPU_REAR_TOWER"
  line L0 (88, -214, 520) -> (90, -212, 520)
  line L1 (90, -212, 520) -> (154, -212, 520)
  line L2 (154, -212, 520) -> (156, -214, 520)
  line L3 (156, -214, 520) -> (156, -308, 520)
  line L4 (156, -308, 520) -> (154, -310, 520)
  line L5 (154, -310, 520) -> (90, -310, 520)
  line L6 (90, -310, 520) -> (88, -308, 520)
  line L7 (88, -308, 520) -> (88, -214, 520)
extrude "Display connector window" cut sketch "草图4 (9)" along normal blind 8 contours L0 L1 L2 L3 L4 L5 L6 L7 in plane through (0, 260, 0) normal (0, 1, 0) bodies 17 in component "07_GPU_REAR_TOWER"
ref_plane "工作平面5" through (0, -260, 0) normal (0, 1, 0) x (0, 0, 1) in component "07_GPU_REAR_TOWER"
sketch "草图5 (9)" plane through (0, -260, 0) normal (0, 1, 0) x (1, 0, 0) in component "07_GPU_REAR_TOWER"
  circle A0 through (81.7, -316, 520) (79.15, -314.5278, 520) (79.15, -317.4722, 520)
extrude "Bracket height adjustment end1" cut sketch "草图5 (9)" along normal blind 8 contours A0 in plane through (0, 260, 0) normal (0, 1, 0) bodies 17 in component "07_GPU_REAR_TOWER"
ref_plane "工作平面6" through (0, -260, 0) normal (0, 1, 0) x (0, 0, 1) in component "07_GPU_REAR_TOWER"
sketch "草图6 (5)" plane through (0, -260, 0) normal (0, 1, 0) x (1, 0, 0) in component "07_GPU_REAR_TOWER"
  circle A0 through (81.7, -344, 520) (79.15, -342.5278, 520) (79.15, -345.4722, 520)
extrude "Bracket height adjustment end2" cut sketch "草图6 (5)" along normal blind 8 contours A0 in plane through (0, 260, 0) normal (0, 1, 0) bodies 17 in component "07_GPU_REAR_TOWER"
ref_plane "工作平面7" through (0, -260, 0) normal (0, 1, 0) x (0, 0, 1) in component "07_GPU_REAR_TOWER"
sketch "草图7 (5)" plane through (0, -260, 0) normal (0, 1, 0) x (1, 0, 0) in component "07_GPU_REAR_TOWER"
  line L0 (78.3, -316, 520) -> (81.7, -316, 520)
  line L1 (81.7, -316, 520) -> (81.7, -344, 520)
  line L2 (81.7, -344, 520) -> (78.3, -344, 520)
  line L3 (78.3, -344, 520) -> (78.3, -316, 520)
extrude "Bracket height adjustment middle" cut sketch "草图7 (5)" along normal blind 8 contours L0 L1 L2 L3 in plane through (0, 260, 0) normal (0, 1, 0) bodies 17 in component "07_GPU_REAR_TOWER"
ref_plane "工作平面8" through (0, -260, 0) normal (0, 1, 0) x (0, 0, 1) in component "07_GPU_REAR_TOWER"
sketch "草图8 (5)" plane through (0, -260, 0) normal (0, 1, 0) x (1, 0, 0) in component "07_GPU_REAR_TOWER"
  circle A0 through (165.7, -316, 520) (163.15, -314.5278, 520) (163.15, -317.4722, 520)
extrude "Bracket height adjustment end1 (1)" cut sketch "草图8 (5)" along normal blind 8 contours A0 in plane through (0, 260, 0) normal (0, 1, 0) bodies 17 in component "07_GPU_REAR_TOWER"
ref_plane "工作平面9" through (0, -260, 0) normal (0, 1, 0) x (0, 0, 1) in component "07_GPU_REAR_TOWER"
sketch "草图9 (5)" plane through (0, -260, 0) normal (0, 1, 0) x (1, 0, 0) in component "07_GPU_REAR_TOWER"
  circle A0 through (165.7, -344, 520) (163.15, -342.5278, 520) (163.15, -345.4722, 520)
extrude "Bracket height adjustment end2 (1)" cut sketch "草图9 (5)" along normal blind 8 contours A0 in plane through (0, 260, 0) normal (0, 1, 0) bodies 17 in component "07_GPU_REAR_TOWER"
ref_plane "工作平面10" through (0, -260, 0) normal (0, 1, 0) x (0, 0, 1) in component "07_GPU_REAR_TOWER"
sketch "草图10 (3)" plane through (0, -260, 0) normal (0, 1, 0) x (1, 0, 0) in component "07_GPU_REAR_TOWER"
  line L0 (162.3, -316, 520) -> (165.7, -316, 520)
  line L1 (165.7, -316, 520) -> (165.7, -344, 520)
  line L2 (165.7, -344, 520) -> (162.3, -344, 520)
  line L3 (162.3, -344, 520) -> (162.3, -316, 520)
extrude "Bracket height adjustment middle (1)" cut sketch "草图10 (3)" along normal blind 8 contours L0 L1 L2 L3 in plane through (0, 260, 0) normal (0, 1, 0) bodies 17 in component "07_GPU_REAR_TOWER"
ref_plane "工作平面1" through (0, 0, 316) normal (0, 0, 1) x (1, 0, 0) in component "08_GPU_REAR_SLIDER"
sketch "草图1 (18)" plane through (0, 0, 316) normal (0, 0, 1) x (1, 0, 0) in component "08_GPU_REAR_SLIDER"
  line L0 (74, 250) -> (170, 250)
  line L1 (170, 250) -> (170, 260)
  line L2 (170, 260) -> (74, 260)
  line L3 (74, 260) -> (74, 250)
extrude "GPU rear sliding carrier" add sketch "草图1 (18)" along normal blind 30 separate body makes body 18 in component "08_GPU_REAR_SLIDER"
ref_plane "工作平面2" through (0, 0, 330) normal (0, 0, 1) x (1, 0, 0) in component "08_GPU_REAR_SLIDER"
sketch "草图2 (14)" plane through (0, 0, 330) normal (0, 0, 1) x (1, 0, 0) in component "08_GPU_REAR_SLIDER"
  line L0 (74, 244.84) -> (170, 244.84)
  line L1 (170, 244.84) -> (170, 250)
  line L2 (170, 250) -> (74, 250)
  line L3 (74, 250) -> (74, 244.84)
extrude "GPU screw ledge" add sketch "草图2 (14)" along normal blind 6 bodies 18 in component "08_GPU_REAR_SLIDER"
ref_plane "工作平面3" through (0, 0, 316) normal (0, 0, 1) x (1, 0, 0) in component "08_GPU_REAR_SLIDER"
sketch "草图3 (10)" plane through (0, 0, 316) normal (0, 0, 1) x (1, 0, 0) in component "08_GPU_REAR_SLIDER"
  line L0 (89, 250) -> (155, 250)
  line L1 (155, 250) -> (155, 260)
  line L2 (155, 260) -> (89, 260)
  line L3 (89, 260) -> (89, 250)
extrude "Keep display plug path open" cut sketch "草图3 (10)" along normal blind 13 bodies 18 in component "08_GPU_REAR_SLIDER"
ref_plane "工作平面4" through (0, 0, 330) normal (0, 0, 1) x (1, 0, 0) in component "08_GPU_REAR_SLIDER"
sketch "草图4 (10)" plane through (0, 0, 330) normal (0, 0, 1) x (1, 0, 0) in component "08_GPU_REAR_SLIDER"
  circle A0 centre (90, 247.5) radius 1.7
extrude "GPU screw slot first end" cut sketch "草图4 (10)" along normal blind 6 bodies 18 in component "08_GPU_REAR_SLIDER"
ref_plane "工作平面5" through (0, 0, 330) normal (0, 0, 1) x (1, 0, 0) in component "08_GPU_REAR_SLIDER"
sketch "草图5 (10)" plane through (0, 0, 330) normal (0, 0, 1) x (1, 0, 0) in component "08_GPU_REAR_SLIDER"
  circle A0 centre (154, 247.5) radius 1.7
extrude "GPU screw slot second end" cut sketch "草图5 (10)" along normal blind 6 bodies 18 in component "08_GPU_REAR_SLIDER"
ref_plane "工作平面6" through (0, 0, 330) normal (0, 0, 1) x (1, 0, 0) in component "08_GPU_REAR_SLIDER"
sketch "草图6 (6)" plane through (0, 0, 330) normal (0, 0, 1) x (1, 0, 0) in component "08_GPU_REAR_SLIDER"
  line L0 (90, 245.8) -> (154, 245.8)
  line L1 (154, 245.8) -> (154, 249.2)
  line L2 (154, 249.2) -> (90, 249.2)
  line L3 (90, 249.2) -> (90, 245.8)
extrude "GPU screw transverse slot" cut sketch "草图6 (6)" along normal blind 6 bodies 18 in component "08_GPU_REAR_SLIDER"
ref_plane "工作平面1" through (0, 0, 198) normal (0, 0, 1) x (1, 0, 0) in component "09_FRONT_DUAL_FAN_CARRIER"
sketch "草图1 (19)" plane through (0, 0, 198) normal (0, 0, 1) x (1, 0, 0) in component "09_FRONT_DUAL_FAN_CARRIER"
  line L0 (12.4, -25) -> (296.4, -25)
  line L1 (296.4, -25) -> (296.4, -19)
  line L2 (296.4, -19) -> (12.4, -19)
  line L3 (12.4, -19) -> (12.4, -25)
extrude "Common 284 mm wide fan carrier" add sketch "草图1 (19)" along normal blind 12 separate body makes body 19 in component "09_FRONT_DUAL_FAN_CARRIER"
ref_plane "工作平面2" through (0, 0, 198) normal (0, 0, 1) x (1, 0, 0) in component "09_FRONT_DUAL_FAN_CARRIER"
sketch "草图2 (15)" plane through (0, 0, 198) normal (0, 0, 1) x (1, 0, 0) in component "09_FRONT_DUAL_FAN_CARRIER"
  line L0 (45, -19) -> (55, -19)
  line L1 (55, -19) -> (55, 14)
  line L2 (55, 14) -> (45, 14)
  line L3 (45, 14) -> (45, -19)
extrude "Fan carrier arm onto front beam" add sketch "草图2 (15)" along normal blind 6 bodies 19 in component "09_FRONT_DUAL_FAN_CARRIER"
ref_plane "工作平面3" through (45, 0, 0) normal (1, 0, 0) x (0, 1, 0) in component "09_FRONT_DUAL_FAN_CARRIER"
sketch "草图3 (11)" plane through (45, 0, 0) normal (1, 0, 0) x (0, 0, -1) in component "09_FRONT_DUAL_FAN_CARRIER"
  line L0 (-198, -25) -> (-184, -19)
  line L1 (-184, -19) -> (-198, -2.65)
  line L2 (-198, -2.65) -> (-198, -25)
extrude "Fan carrier arm gusset" add sketch "草图3 (11)" along normal blind 10 bodies 19 in component "09_FRONT_DUAL_FAN_CARRIER"
ref_plane "工作平面4" through (0, 0, 198) normal (0, 0, 1) x (1, 0, 0) in component "09_FRONT_DUAL_FAN_CARRIER"
sketch "草图4 (11)" plane through (0, 0, 198) normal (0, 0, 1) x (1, 0, 0) in component "09_FRONT_DUAL_FAN_CARRIER"
  line L0 (149.4, -19) -> (159.4, -19)
  line L1 (159.4, -19) -> (159.4, 14)
  line L2 (159.4, 14) -> (149.4, 14)
  line L3 (149.4, 14) -> (149.4, -19)
extrude "Fan carrier arm onto front beam (1)" add sketch "草图4 (11)" along normal blind 6 bodies 19 in component "09_FRONT_DUAL_FAN_CARRIER"
ref_plane "工作平面5" through (149.4, 0, 0) normal (1, 0, 0) x (0, 1, 0) in component "09_FRONT_DUAL_FAN_CARRIER"
sketch "草图5 (11)" plane through (149.4, 0, 0) normal (1, 0, 0) x (0, 0, -1) in component "09_FRONT_DUAL_FAN_CARRIER"
  line L0 (-198, -25) -> (-184, -19)
  line L1 (-184, -19) -> (-198, -2.65)
  line L2 (-198, -2.65) -> (-198, -25)
extrude "Fan carrier arm gusset (1)" add sketch "草图5 (11)" along normal blind 10 bodies 19 in component "09_FRONT_DUAL_FAN_CARRIER"
ref_plane "工作平面6" through (0, 0, 198) normal (0, 0, 1) x (1, 0, 0) in component "09_FRONT_DUAL_FAN_CARRIER"
sketch "草图6 (7)" plane through (0, 0, 198) normal (0, 0, 1) x (1, 0, 0) in component "09_FRONT_DUAL_FAN_CARRIER"
  line L0 (260, -19) -> (270, -19)
  line L1 (270, -19) -> (270, 14)
  line L2 (270, 14) -> (260, 14)
  line L3 (260, 14) -> (260, -19)
extrude "Fan carrier arm onto front beam (2)" add sketch "草图6 (7)" along normal blind 6 bodies 19 in component "09_FRONT_DUAL_FAN_CARRIER"
ref_plane "工作平面7" through (260, 0, 0) normal (1, 0, 0) x (0, 1, 0) in component "09_FRONT_DUAL_FAN_CARRIER"
sketch "草图7 (6)" plane through (260, 0, 0) normal (1, 0, 0) x (0, 0, -1) in component "09_FRONT_DUAL_FAN_CARRIER"
  line L0 (-198, -25) -> (-184, -19)
  line L1 (-184, -19) -> (-198, -2.65)
  line L2 (-198, -2.65) -> (-198, -25)
extrude "Fan carrier arm gusset (2)" add sketch "草图7 (6)" along normal blind 10 bodies 19 in component "09_FRONT_DUAL_FAN_CARRIER"
ref_plane "工作平面1" through (0, 25, 0) normal (0, 1, 0) x (0, 0, 1) in component "10_GPU_140_FAN_MOUNT"
sketch "草图1 (20)" plane through (0, 25, 0) normal (0, 1, 0) x (1, 0, 0) in component "10_GPU_140_FAN_MOUNT"
  line L0 (12.4, -210, -50) -> (152.4, -210, -50)
  line L1 (152.4, -210, -50) -> (152.4, -350, -50)
  line L2 (152.4, -350, -50) -> (12.4, -350, -50)
  line L3 (12.4, -350, -50) -> (12.4, -210, -50)
extrude "140 mm removable fan mounting frame" add sketch "草图1 (20)" along normal blind 6 separate body contours L0 L1 L2 L3 in plane through (0, -25, 0) normal (0, 1, 0) makes body 20 in component "10_GPU_140_FAN_MOUNT"
ref_plane "工作平面2" through (0, 25, 0) normal (0, 1, 0) x (0, 0, 1) in component "10_GPU_140_FAN_MOUNT"
sketch "草图2 (16)" plane through (0, 25, 0) normal (0, 1, 0) x (1, 0, 0) in component "10_GPU_140_FAN_MOUNT"
  circle A0 through (147.4, -280, -50) (49.9, -223.7083, -50) (49.9, -336.2917, -50)
extrude "Open airflow aperture" cut sketch "草图2 (16)" along normal blind 6 contours A0 in plane through (0, -25, 0) normal (0, 1, 0) bodies 20 in component "10_GPU_140_FAN_MOUNT"
ref_plane "工作平面3" through (0, 25, 0) normal (0, 1, 0) x (0, 0, 1) in component "10_GPU_140_FAN_MOUNT"
sketch "草图3 (12)" plane through (0, 25, 0) normal (0, 1, 0) x (1, 0, 0) in component "10_GPU_140_FAN_MOUNT"
  circle A0 through (22.4, -217.75, -50) (19.025, -215.8014, -50) (19.025, -219.6986, -50)
extrude "124.5 mm pitch fan fixing clearance" cut sketch "草图3 (12)" along normal blind 6 contours A0 in plane through (0, -25, 0) normal (0, 1, 0) bodies 20 in component "10_GPU_140_FAN_MOUNT"
ref_plane "工作平面4" through (0, 25, 0) normal (0, 1, 0) x (0, 0, 1) in component "10_GPU_140_FAN_MOUNT"
sketch "草图4 (12)" plane through (0, 25, 0) normal (0, 1, 0) x (1, 0, 0) in component "10_GPU_140_FAN_MOUNT"
  circle A0 through (22.4, -342.25, -50) (19.025, -340.3014, -50) (19.025, -344.1986, -50)
extrude "124.5 mm pitch fan fixing clearance (1)" cut sketch "草图4 (12)" along normal blind 6 contours A0 in plane through (0, -25, 0) normal (0, 1, 0) bodies 20 in component "10_GPU_140_FAN_MOUNT"
ref_plane "工作平面5" through (0, 25, 0) normal (0, 1, 0) x (0, 0, 1) in component "10_GPU_140_FAN_MOUNT"
sketch "草图5 (12)" plane through (0, 25, 0) normal (0, 1, 0) x (1, 0, 0) in component "10_GPU_140_FAN_MOUNT"
  circle A0 through (146.9, -217.75, -50) (143.525, -215.8014, -50) (143.525, -219.6986, -50)
extrude "124.5 mm pitch fan fixing clearance (2)" cut sketch "草图5 (12)" along normal blind 6 contours A0 in plane through (0, -25, 0) normal (0, 1, 0) bodies 20 in component "10_GPU_140_FAN_MOUNT"
ref_plane "工作平面6" through (0, 25, 0) normal (0, 1, 0) x (0, 0, 1) in component "10_GPU_140_FAN_MOUNT"